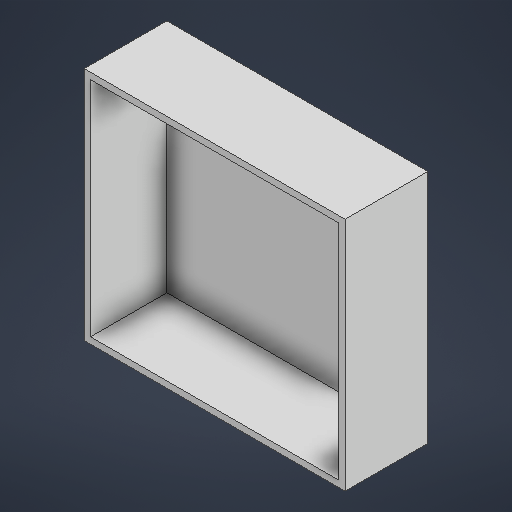
# Autodesk Inventor part: Front
Saved by Autodesk Inventor 2027 (Build 310192060, 192F)
## iProperties
Created: 2026-10-17
Part Number: Front
Material: Générique
Document SubType Name: Modeling
Designer: strei
Density: 1 g/cm^3
Appearance: Par défaut
Author: strei
Autodesk Inventor part; units mm, degrees
ref_plane "YZ Plane" through (0, 0, 0) normal (1, 0, 0) x (0, 1, 0)
ref_plane "XZ Plane" through (0, 0, 0) normal (0, 1, 0) x (-1, 0, 0)
ref_plane "XY Plane" through (0, 0, 0) normal (0, 0, 1) x (1, 0, 0)
sketch "Esquisse1" plane through (0, 0, 0) normal (0, 0, 1) x (1, 0, 0)
  line L0 (-390, 350) -> (390, 350)
  line L1 (390, 350) -> (390, -350)
  line L2 (390, -350) -> (-390, -350)
  line L3 (-390, -350) -> (-390, 350)
  line L4 (-390, 350) -> (390, -350) construction
  line L5 (390, 350) -> (-390, -350) construction
  point P0 (0, 0)
  point P1 (0, 0)
  point P2 (0, -350)
  dimension "d0" = 780
  dimension "d1" = 700
  constraints: 12 end point, 3 midpoint, 2 parallel, 1 coincident, 1 horizontal, 1 perpendicular
  measures "d0" distance of L1.end L2.end
  measures "d1" distance of L0.end L1.end
extrude "Extrusion1" add sketch "Esquisse1" along normal mid plane 240
shell "Coque1" thickness 20 outward yes removed faces 1 at (130, -116.6667, 120)
